Autodesk Fusion 360 part; units mm, degrees
(part 6 of 6)
sketch "Skizze11" plane through (0, 0, 0) normal (0, 1, 0) x (1, 0, 0)
  spline S0 degree 5 poles (100, -0.126) (99.9798, -0.1288) (99.9313, -0.1355) (99.8343, -0.1489) (99.6563, -0.1737) (99.3616, -0.2148) (99.015, -0.2631) (98.6371, -0.3154) (98.2386, -0.3703) (97.8209, -0.4275) (97.382, -0.4873) (96.9201, -0.55) (96.4368, -0.6152) (95.9348, -0.6827) (95.4173, -0.7517) (94.8865, -0.8221) (94.3434, -0.8935) (93.7883, -0.966) (93.2211, -1.0395) (92.6419, -1.1139) (92.0509, -1.1893) (91.4489, -1.2656) (90.8365, -1.3428) (90.2145, -1.4207) (89.5836, -1.4992) (88.9442, -1.5783) (88.2966, -1.6578) (87.6411, -1.7376) (86.9779, -1.8177) (86.3071, -1.898) (85.6291, -1.9785) (84.9441, -2.0592) (84.2524, -2.14) (83.5542, -2.2209) (82.8499, -2.302) (82.1396, -2.3832) (81.4237, -2.4644) (80.7023, -2.5455) (79.9756, -2.6264) (79.2439, -2.7072) (78.5072, -2.7876) (77.7658, -2.8678) (77.0199, -2.9476) (76.2696, -3.0272) (75.5151, -3.1065) (74.7565, -3.1855) (73.994, -3.2641) (73.2278, -3.3425) (72.458, -3.4204) (71.6848, -3.498) (70.9082, -3.5751) (70.1285, -3.6516) (69.3457, -3.7276) (68.5601, -3.8029) (67.7717, -3.8776) (66.9807, -3.9517) (66.1873, -4.025) (65.3915, -4.0976) (64.5935, -4.1695) (63.7933, -4.2406) (62.9912, -4.3109) (62.1872, -4.3803) (61.3815, -4.4489) (60.5741, -4.5165) (59.7651, -4.5832) (58.9548, -4.6489) (58.1431, -4.7135) (57.3303, -4.7772) (56.5164, -4.8397) (55.7016, -4.9011) (54.886, -4.9613) (54.0697, -5.0203) (53.2528, -5.078) (52.4355, -5.1344) (51.6179, -5.1895) (50.7999, -5.2432) (49.9819, -5.2955) (49.1638, -5.3463) (48.3457, -5.3956) (47.5278, -5.4433) (46.7102, -5.4895) (45.893, -5.5341) (45.0762, -5.577) (44.26, -5.6182) (43.4446, -5.6576) (42.63, -5.6953) (41.8164, -5.7311) (41.0039, -5.7649) (40.1926, -5.7967) (39.3826, -5.8264) (38.5742, -5.854) (37.7673, -5.8795) (36.9621, -5.9027) (36.1587, -5.9236) (35.3572, -5.9422) (34.5578, -5.9584) (33.7606, -5.9723) (32.9656, -5.9836) (32.1731, -5.9924) (31.3832, -5.9986) (30.596, -6.0021) (29.8117, -6.0029) (29.0304, -6.0008) (28.2522, -5.9958) (27.4773, -5.9879) (26.7059, -5.9771) (25.9381, -5.9631) (25.1741, -5.9461) (24.4139, -5.926) (23.6579, -5.9026) (22.9062, -5.876) (22.1589, -5.846) (21.4162, -5.8125) (20.6784, -5.7755) (19.9455, -5.7349) (19.218, -5.6907) (18.4958, -5.6427) (17.7792, -5.5908) (17.0686, -5.5351) (16.364, -5.4755) (15.6657, -5.4117) (14.974, -5.3438) (14.2893, -5.2716) (13.6117, -5.195) (12.9416, -5.1138) (12.2793, -5.028) (11.6251, -4.9374) (10.9794, -4.8419) (10.3425, -4.7414) (9.7148, -4.6358) (9.0967, -4.5249) (8.4888, -4.4086) (7.8916, -4.2868) (7.3058, -4.1591) (6.7319, -4.0253) (6.1705, -3.8852) (5.6223, -3.7383) (5.0877, -3.5844) (4.5676, -3.4228) (4.0631, -3.2534) (3.5755, -3.0757) (3.1066, -2.8893) (2.6585, -2.6938) (2.2329, -2.4884) (1.8313, -2.2718) (1.4554, -2.0423) (1.1078, -1.7986) (0.7933, -1.5393) (0.5196, -1.2639) (0.2958, -0.9725) (0.1296, -0.6653) (0.0462, -0.407) (0.012, -0.2062) (0.0019, -0.0693) (0, 0) knots 0 0 0 0 0 0 0.00666667 0.01333333 0.02 0.02666667 0.03333333 0.04 0.04666667 0.05333333 0.06 0.06666667 0.07333333 0.08 0.08666667 0.09333333 0.1 0.10666667 0.11333333 0.12 0.12666667 0.13333333 0.14 0.14666667 0.15333333 0.16 0.16666667 0.17333333 0.18 0.18666667 0.19333333 0.2 0.20666667 0.21333333 0.22 0.22666667 0.23333333 0.24 0.24666667 0.25333333 0.26 0.26666667 0.27333333 0.28 0.28666667 0.29333333 0.3 0.30666667 0.31333333 0.32 0.32666667 0.33333333 0.34 0.34666667 0.35333333 0.36 0.36666667 0.37333333 0.38 0.38666667 0.39333333 0.4 0.40666667 0.41333333 0.42 0.42666667 0.43333333 0.44 0.44666667 0.45333333 0.46 0.46666667 0.47333333 0.48 0.48666667 0.49333333 0.5 0.50666667 0.51333333 0.52 0.52666667 0.53333333 0.54 0.54666667 0.55333333 0.56 0.56666667 0.57333333 0.58 0.58666667 0.59333333 0.6 0.60666667 0.61333333 0.62 0.62666667 0.63333333 0.64 0.64666667 0.65333333 0.66 0.66666667 0.67333333 0.68 0.68666667 0.69333333 0.7 0.70666667 0.71333333 0.72 0.72666667 0.73333333 0.74 0.74666667 0.75333333 0.76 0.76666667 0.77333333 0.78 0.78666667 0.79333333 0.8 0.80666667 0.81333333 0.82 0.82666667 0.83333333 0.84 0.84666667 0.85333333 0.86 0.86666667 0.87333333 0.88 0.88666667 0.89333333 0.9 0.90666667 0.91333333 0.92 0.92666667 0.93333333 0.94 0.94666667 0.95333333 0.96 0.96666667 0.97333333 0.98 0.98666667 0.99333333 1 1 1 1 1 1
  spline S1 degree 5 poles (0, 0) (0.0019, 0.0693) (0.012, 0.2062) (0.0462, 0.407) (0.1296, 0.6653) (0.2958, 0.9725) (0.5196, 1.2639) (0.7933, 1.5393) (1.1078, 1.7986) (1.4554, 2.0423) (1.8313, 2.2718) (2.2329, 2.4884) (2.6585, 2.6938) (3.1066, 2.8893) (3.5755, 3.0757) (4.0631, 3.2534) (4.5676, 3.4228) (5.0877, 3.5844) (5.6223, 3.7383) (6.1705, 3.8852) (6.7319, 4.0253) (7.3058, 4.1591) (7.8916, 4.2868) (8.4888, 4.4086) (9.0967, 4.5249) (9.7148, 4.6358) (10.3425, 4.7414) (10.9794, 4.8419) (11.6251, 4.9374) (12.2793, 5.028) (12.9416, 5.1138) (13.6117, 5.195) (14.2893, 5.2716) (14.974, 5.3438) (15.6657, 5.4117) (16.364, 5.4755) (17.0686, 5.5351) (17.7792, 5.5908) (18.4958, 5.6427) (19.218, 5.6907) (19.9455, 5.7349) (20.6784, 5.7755) (21.4162, 5.8125) (22.1589, 5.846) (22.9062, 5.876) (23.6579, 5.9026) (24.4139, 5.926) (25.1741, 5.9461) (25.9381, 5.9631) (26.7059, 5.9771) (27.4773, 5.9879) (28.2522, 5.9958) (29.0304, 6.0008) (29.8117, 6.0029) (30.596, 6.0021) (31.3832, 5.9986) (32.1731, 5.9924) (32.9656, 5.9836) (33.7606, 5.9723) (34.5578, 5.9584) (35.3572, 5.9422) (36.1587, 5.9236) (36.9621, 5.9027) (37.7673, 5.8795) (38.5742, 5.854) (39.3826, 5.8264) (40.1926, 5.7967) (41.0039, 5.7649) (41.8164, 5.7311) (42.63, 5.6953) (43.4446, 5.6576) (44.26, 5.6182) (45.0762, 5.577) (45.893, 5.5341) (46.7102, 5.4895) (47.5278, 5.4433) (48.3457, 5.3956) (49.1638, 5.3463) (49.9819, 5.2955) (50.7999, 5.2432) (51.6179, 5.1895) (52.4355, 5.1344) (53.2528, 5.078) (54.0697, 5.0203) (54.886, 4.9613) (55.7016, 4.9011) (56.5164, 4.8397) (57.3303, 4.7772) (58.1431, 4.7135) (58.9548, 4.6489) (59.7651, 4.5832) (60.5741, 4.5165) (61.3815, 4.4489) (62.1872, 4.3803) (62.9912, 4.3109) (63.7933, 4.2406) (64.5935, 4.1695) (65.3915, 4.0976) (66.1873, 4.025) (66.9807, 3.9517) (67.7717, 3.8776) (68.5601, 3.8029) (69.3457, 3.7276) (70.1285, 3.6516) (70.9082, 3.5751) (71.6848, 3.498) (72.458, 3.4204) (73.2278, 3.3425) (73.994, 3.2641) (74.7565, 3.1855) (75.5151, 3.1065) (76.2696, 3.0272) (77.0199, 2.9476) (77.7658, 2.8678) (78.5072, 2.7876) (79.2439, 2.7072) (79.9756, 2.6264) (80.7023, 2.5455) (81.4237, 2.4644) (82.1396, 2.3832) (82.8499, 2.302) (83.5542, 2.2209) (84.2524, 2.14) (84.9441, 2.0592) (85.6291, 1.9785) (86.3071, 1.898) (86.9779, 1.8177) (87.6411, 1.7376) (88.2966, 1.6578) (88.9442, 1.5783) (89.5836, 1.4992) (90.2145, 1.4207) (90.8365, 1.3428) (91.4489, 1.2656) (92.0509, 1.1893) (92.6419, 1.1139) (93.2211, 1.0395) (93.7883, 0.966) (94.3434, 0.8935) (94.8865, 0.8221) (95.4173, 0.7517) (95.9348, 0.6827) (96.4368, 0.6152) (96.9201, 0.55) (97.382, 0.4873) (97.8209, 0.4275) (98.2386, 0.3703) (98.6371, 0.3154) (99.015, 0.2631) (99.3616, 0.2148) (99.6563, 0.1737) (99.8343, 0.1489) (99.9313, 0.1355) (99.9798, 0.1288) (100, 0.126) knots 0 0 0 0 0 0 0.00666667 0.01333333 0.02 0.02666667 0.03333333 0.04 0.04666667 0.05333333 0.06 0.06666667 0.07333333 0.08 0.08666667 0.09333333 0.1 0.10666667 0.11333333 0.12 0.12666667 0.13333333 0.14 0.14666667 0.15333333 0.16 0.16666667 0.17333333 0.18 0.18666667 0.19333333 0.2 0.20666667 0.21333333 0.22 0.22666667 0.23333333 0.24 0.24666667 0.25333333 0.26 0.26666667 0.27333333 0.28 0.28666667 0.29333333 0.3 0.30666667 0.31333333 0.32 0.32666667 0.33333333 0.34 0.34666667 0.35333333 0.36 0.36666667 0.37333333 0.38 0.38666667 0.39333333 0.4 0.40666667 0.41333333 0.42 0.42666667 0.43333333 0.44 0.44666667 0.45333333 0.46 0.46666667 0.47333333 0.48 0.48666667 0.49333333 0.5 0.50666667 0.51333333 0.52 0.52666667 0.53333333 0.54 0.54666667 0.55333333 0.56 0.56666667 0.57333333 0.58 0.58666667 0.59333333 0.6 0.60666667 0.61333333 0.62 0.62666667 0.63333333 0.64 0.64666667 0.65333333 0.66 0.66666667 0.67333333 0.68 0.68666667 0.69333333 0.7 0.70666667 0.71333333 0.72 0.72666667 0.73333333 0.74 0.74666667 0.75333333 0.76 0.76666667 0.77333333 0.78 0.78666667 0.79333333 0.8 0.80666667 0.81333333 0.82 0.82666667 0.83333333 0.84 0.84666667 0.85333333 0.86 0.86666667 0.87333333 0.88 0.88666667 0.89333333 0.9 0.90666667 0.91333333 0.92 0.92666667 0.93333333 0.94 0.94666667 0.95333333 0.96 0.96666667 0.97333333 0.98 0.98666667 0.99333333 1 1 1 1 1 1
  line L0 (100, 0.126) -> (100, -0.126)
  point P0 (99.726, -0.164)
  point P1 (98.907, -0.278)
  point P2 (97.553, -0.464)
  point P3 (95.677, -0.717)
  point P4 (93.301, -1.029)
  point P5 (90.451, -1.391)
  point P6 (87.157, -1.796)
  point P7 (83.457, -2.232)
  point P8 (79.389, -2.691)
  point P9 (75, -3.16)
  point P10 (70.337, -3.631)
  point P11 (65.451, -4.092)
  point P12 (60.396, -4.531)
  point P13 (55.226, -4.936)
  point P14 (50, -5.294)
  point P15 (44.774, -5.592)
  point P16 (39.604, -5.818)
  point P17 (34.549, -5.958)
  point P18 (29.663, -6.002)
  point P19 (25, -5.941)
  point P20 (20.611, -5.771)
  point P21 (16.544, -5.49)
  point P22 (12.843, -5.1)
  point P23 (9.549, -4.605)
  point P24 (6.699, -4.015)
  point P25 (4.323, -3.339)
  point P26 (2.447, -2.589)
  point P27 (1.093, -1.777)
  point P28 (0.274, -0.911)
  point P29 (0.274, 0.911)
  point P30 (1.093, 1.777)
  point P31 (2.447, 2.589)
  point P32 (4.323, 3.339)
  point P33 (6.699, 4.015)
  point P34 (9.549, 4.605)
  point P35 (12.843, 5.1)
  point P36 (16.544, 5.49)
  point P37 (20.611, 5.771)
  point P38 (25, 5.941)
  point P39 (29.663, 6.002)
  point P40 (34.549, 5.958)
  point P41 (39.604, 5.818)
  point P42 (44.774, 5.592)
  point P43 (50, 5.294)
  point P44 (55.226, 4.936)
  point P45 (60.396, 4.531)
  point P46 (65.451, 4.092)
  point P47 (70.337, 3.631)
  point P48 (75, 3.16)
  point P49 (79.389, 2.691)
  point P50 (83.457, 2.232)
  point P51 (87.157, 1.796)
  point P52 (90.451, 1.391)
  point P53 (93.301, 1.029)
  point P54 (95.677, 0.717)
  point P55 (97.553, 0.464)
  point P56 (98.907, 0.278)
  point P57 (99.726, 0.164)
surface "Schnitt_SLW_Wurzel" add patch profiles "Skizze11" section 1 separate body makes body 19
scale "Profiltiefe_SLW_Wurzel" factor 2.2 about (0, 0, 0) bodies 19
sketch "Skizze12" plane through (0, 0, 0) normal (0, 1, 0) x (1, 0, 0)
  spline S0 degree 5 poles (100, -0.126) (99.9798, -0.1288) (99.9313, -0.1355) (99.8343, -0.1489) (99.6563, -0.1737) (99.3616, -0.2148) (99.015, -0.2631) (98.6371, -0.3154) (98.2386, -0.3703) (97.8209, -0.4275) (97.382, -0.4873) (96.9201, -0.55) (96.4368, -0.6152) (95.9348, -0.6827) (95.4173, -0.7517) (94.8865, -0.8221) (94.3434, -0.8935) (93.7883, -0.966) (93.2211, -1.0395) (92.6419, -1.1139) (92.0509, -1.1893) (91.4489, -1.2656) (90.8365, -1.3428) (90.2145, -1.4207) (89.5836, -1.4992) (88.9442, -1.5783) (88.2966, -1.6578) (87.6411, -1.7376) (86.9779, -1.8177) (86.3071, -1.898) (85.6291, -1.9785) (84.9441, -2.0592) (84.2524, -2.14) (83.5542, -2.2209) (82.8499, -2.302) (82.1396, -2.3832) (81.4237, -2.4644) (80.7023, -2.5455) (79.9756, -2.6264) (79.2439, -2.7072) (78.5072, -2.7876) (77.7658, -2.8678) (77.0199, -2.9476) (76.2696, -3.0272) (75.5151, -3.1065) (74.7565, -3.1855) (73.994, -3.2641) (73.2278, -3.3425) (72.458, -3.4204) (71.6848, -3.498) (70.9082, -3.5751) (70.1285, -3.6516) (69.3457, -3.7276) (68.5601, -3.8029) (67.7717, -3.8776) (66.9807, -3.9517) (66.1873, -4.025) (65.3915, -4.0976) (64.5935, -4.1695) (63.7933, -4.2406) (62.9912, -4.3109) (62.1872, -4.3803) (61.3815, -4.4489) (60.5741, -4.5165) (59.7651, -4.5832) (58.9548, -4.6489) (58.1431, -4.7135) (57.3303, -4.7772) (56.5164, -4.8397) (55.7016, -4.9011) (54.886, -4.9613) (54.0697, -5.0203) (53.2528, -5.078) (52.4355, -5.1344) (51.6179, -5.1895) (50.7999, -5.2432) (49.9819, -5.2955) (49.1638, -5.3463) (48.3457, -5.3956) (47.5278, -5.4433) (46.7102, -5.4895) (45.893, -5.5341) (45.0762, -5.577) (44.26, -5.6182) (43.4446, -5.6576) (42.63, -5.6953) (41.8164, -5.7311) (41.0039, -5.7649) (40.1926, -5.7967) (39.3826, -5.8264) (38.5742, -5.854) (37.7673, -5.8795) (36.9621, -5.9027) (36.1587, -5.9236) (35.3572, -5.9422) (34.5578, -5.9584) (33.7606, -5.9723) (32.9656, -5.9836) (32.1731, -5.9924) (31.3832, -5.9986) (30.596, -6.0021) (29.8117, -6.0029) (29.0304, -6.0008) (28.2522, -5.9958) (27.4773, -5.9879) (26.7059, -5.9771) (25.9381, -5.9631) (25.1741, -5.9461) (24.4139, -5.926) (23.6579, -5.9026) (22.9062, -5.876) (22.1589, -5.846) (21.4162, -5.8125) (20.6784, -5.7755) (19.9455, -5.7349) (19.218, -5.6907) (18.4958, -5.6427) (17.7792, -5.5908) (17.0686, -5.5351) (16.364, -5.4755) (15.6657, -5.4117) (14.974, -5.3438) (14.2893, -5.2716) (13.6117, -5.195) (12.9416, -5.1138) (12.2793, -5.028) (11.6251, -4.9374) (10.9794, -4.8419) (10.3425, -4.7414) (9.7148, -4.6358) (9.0967, -4.5249) (8.4888, -4.4086) (7.8916, -4.2868) (7.3058, -4.1591) (6.7319, -4.0253) (6.1705, -3.8852) (5.6223, -3.7383) (5.0877, -3.5844) (4.5676, -3.4228) (4.0631, -3.2534) (3.5755, -3.0757) (3.1066, -2.8893) (2.6585, -2.6938) (2.2329, -2.4884) (1.8313, -2.2718) (1.4554, -2.0423) (1.1078, -1.7986) (0.7933, -1.5393) (0.5196, -1.2639) (0.2958, -0.9725) (0.1296, -0.6653) (0.0462, -0.407) (0.012, -0.2062) (0.0019, -0.0693) (0, 0) knots 0 0 0 0 0 0 0.00666667 0.01333333 0.02 0.02666667 0.03333333 0.04 0.04666667 0.05333333 0.06 0.06666667 0.07333333 0.08 0.08666667 0.09333333 0.1 0.10666667 0.11333333 0.12 0.12666667 0.13333333 0.14 0.14666667 0.15333333 0.16 0.16666667 0.17333333 0.18 0.18666667 0.19333333 0.2 0.20666667 0.21333333 0.22 0.22666667 0.23333333 0.24 0.24666667 0.25333333 0.26 0.26666667 0.27333333 0.28 0.28666667 0.29333333 0.3 0.30666667 0.31333333 0.32 0.32666667 0.33333333 0.34 0.34666667 0.35333333 0.36 0.36666667 0.37333333 0.38 0.38666667 0.39333333 0.4 0.40666667 0.41333333 0.42 0.42666667 0.43333333 0.44 0.44666667 0.45333333 0.46 0.46666667 0.47333333 0.48 0.48666667 0.49333333 0.5 0.50666667 0.51333333 0.52 0.52666667 0.53333333 0.54 0.54666667 0.55333333 0.56 0.56666667 0.57333333 0.58 0.58666667 0.59333333 0.6 0.60666667 0.61333333 0.62 0.62666667 0.63333333 0.64 0.64666667 0.65333333 0.66 0.66666667 0.67333333 0.68 0.68666667 0.69333333 0.7 0.70666667 0.71333333 0.72 0.72666667 0.73333333 0.74 0.74666667 0.75333333 0.76 0.76666667 0.77333333 0.78 0.78666667 0.79333333 0.8 0.80666667 0.81333333 0.82 0.82666667 0.83333333 0.84 0.84666667 0.85333333 0.86 0.86666667 0.87333333 0.88 0.88666667 0.89333333 0.9 0.90666667 0.91333333 0.92 0.92666667 0.93333333 0.94 0.94666667 0.95333333 0.96 0.96666667 0.97333333 0.98 0.98666667 0.99333333 1 1 1 1 1 1
  spline S1 degree 5 poles (0, 0) (0.0019, 0.0693) (0.012, 0.2062) (0.0462, 0.407) (0.1296, 0.6653) (0.2958, 0.9725) (0.5196, 1.2639) (0.7933, 1.5393) (1.1078, 1.7986) (1.4554, 2.0423) (1.8313, 2.2718) (2.2329, 2.4884) (2.6585, 2.6938) (3.1066, 2.8893) (3.5755, 3.0757) (4.0631, 3.2534) (4.5676, 3.4228) (5.0877, 3.5844) (5.6223, 3.7383) (6.1705, 3.8852) (6.7319, 4.0253) (7.3058, 4.1591) (7.8916, 4.2868) (8.4888, 4.4086) (9.0967, 4.5249) (9.7148, 4.6358) (10.3425, 4.7414) (10.9794, 4.8419) (11.6251, 4.9374) (12.2793, 5.028) (12.9416, 5.1138) (13.6117, 5.195) (14.2893, 5.2716) (14.974, 5.3438) (15.6657, 5.4117) (16.364, 5.4755) (17.0686, 5.5351) (17.7792, 5.5908) (18.4958, 5.6427) (19.218, 5.6907) (19.9455, 5.7349) (20.6784, 5.7755) (21.4162, 5.8125) (22.1589, 5.846) (22.9062, 5.876) (23.6579, 5.9026) (24.4139, 5.926) (25.1741, 5.9461) (25.9381, 5.9631) (26.7059, 5.9771) (27.4773, 5.9879) (28.2522, 5.9958) (29.0304, 6.0008) (29.8117, 6.0029) (30.596, 6.0021) (31.3832, 5.9986) (32.1731, 5.9924) (32.9656, 5.9836) (33.7606, 5.9723) (34.5578, 5.9584) (35.3572, 5.9422) (36.1587, 5.9236) (36.9621, 5.9027) (37.7673, 5.8795) (38.5742, 5.854) (39.3826, 5.8264) (40.1926, 5.7967) (41.0039, 5.7649) (41.8164, 5.7311) (42.63, 5.6953) (43.4446, 5.6576) (44.26, 5.6182) (45.0762, 5.577) (45.893, 5.5341) (46.7102, 5.4895) (47.5278, 5.4433) (48.3457, 5.3956) (49.1638, 5.3463) (49.9819, 5.2955) (50.7999, 5.2432) (51.6179, 5.1895) (52.4355, 5.1344) (53.2528, 5.078) (54.0697, 5.0203) (54.886, 4.9613) (55.7016, 4.9011) (56.5164, 4.8397) (57.3303, 4.7772) (58.1431, 4.7135) (58.9548, 4.6489) (59.7651, 4.5832) (60.5741, 4.5165) (61.3815, 4.4489) (62.1872, 4.3803) (62.9912, 4.3109) (63.7933, 4.2406) (64.5935, 4.1695) (65.3915, 4.0976) (66.1873, 4.025) (66.9807, 3.9517) (67.7717, 3.8776) (68.5601, 3.8029) (69.3457, 3.7276) (70.1285, 3.6516) (70.9082, 3.5751) (71.6848, 3.498) (72.458, 3.4204) (73.2278, 3.3425) (73.994, 3.2641) (74.7565, 3.1855) (75.5151, 3.1065) (76.2696, 3.0272) (77.0199, 2.9476) (77.7658, 2.8678) (78.5072, 2.7876) (79.2439, 2.7072) (79.9756, 2.6264) (80.7023, 2.5455) (81.4237, 2.4644) (82.1396, 2.3832) (82.8499, 2.302) (83.5542, 2.2209) (84.2524, 2.14) (84.9441, 2.0592) (85.6291, 1.9785) (86.3071, 1.898) (86.9779, 1.8177) (87.6411, 1.7376) (88.2966, 1.6578) (88.9442, 1.5783) (89.5836, 1.4992) (90.2145, 1.4207) (90.8365, 1.3428) (91.4489, 1.2656) (92.0509, 1.1893) (92.6419, 1.1139) (93.2211, 1.0395) (93.7883, 0.966) (94.3434, 0.8935) (94.8865, 0.8221) (95.4173, 0.7517) (95.9348, 0.6827) (96.4368, 0.6152) (96.9201, 0.55) (97.382, 0.4873) (97.8209, 0.4275) (98.2386, 0.3703) (98.6371, 0.3154) (99.015, 0.2631) (99.3616, 0.2148) (99.6563, 0.1737) (99.8343, 0.1489) (99.9313, 0.1355) (99.9798, 0.1288) (100, 0.126) knots 0 0 0 0 0 0 0.00666667 0.01333333 0.02 0.02666667 0.03333333 0.04 0.04666667 0.05333333 0.06 0.06666667 0.07333333 0.08 0.08666667 0.09333333 0.1 0.10666667 0.11333333 0.12 0.12666667 0.13333333 0.14 0.14666667 0.15333333 0.16 0.16666667 0.17333333 0.18 0.18666667 0.19333333 0.2 0.20666667 0.21333333 0.22 0.22666667 0.23333333 0.24 0.24666667 0.25333333 0.26 0.26666667 0.27333333 0.28 0.28666667 0.29333333 0.3 0.30666667 0.31333333 0.32 0.32666667 0.33333333 0.34 0.34666667 0.35333333 0.36 0.36666667 0.37333333 0.38 0.38666667 0.39333333 0.4 0.40666667 0.41333333 0.42 0.42666667 0.43333333 0.44 0.44666667 0.45333333 0.46 0.46666667 0.47333333 0.48 0.48666667 0.49333333 0.5 0.50666667 0.51333333 0.52 0.52666667 0.53333333 0.54 0.54666667 0.55333333 0.56 0.56666667 0.57333333 0.58 0.58666667 0.59333333 0.6 0.60666667 0.61333333 0.62 0.62666667 0.63333333 0.64 0.64666667 0.65333333 0.66 0.66666667 0.67333333 0.68 0.68666667 0.69333333 0.7 0.70666667 0.71333333 0.72 0.72666667 0.73333333 0.74 0.74666667 0.75333333 0.76 0.76666667 0.77333333 0.78 0.78666667 0.79333333 0.8 0.80666667 0.81333333 0.82 0.82666667 0.83333333 0.84 0.84666667 0.85333333 0.86 0.86666667 0.87333333 0.88 0.88666667 0.89333333 0.9 0.90666667 0.91333333 0.92 0.92666667 0.93333333 0.94 0.94666667 0.95333333 0.96 0.96666667 0.97333333 0.98 0.98666667 0.99333333 1 1 1 1 1 1
  line L0 (100, 0.126) -> (100, -0.126)
  point P0 (99.726, -0.164)
  point P1 (98.907, -0.278)
  point P2 (97.553, -0.464)
  point P3 (95.677, -0.717)
  point P4 (93.301, -1.029)
  point P5 (90.451, -1.391)
  point P6 (87.157, -1.796)
  point P7 (83.457, -2.232)
  point P8 (79.389, -2.691)
  point P9 (75, -3.16)
  point P10 (70.337, -3.631)
  point P11 (65.451, -4.092)
  point P12 (60.396, -4.531)
  point P13 (55.226, -4.936)
  point P14 (50, -5.294)
  point P15 (44.774, -5.592)
  point P16 (39.604, -5.818)
  point P17 (34.549, -5.958)
  point P18 (29.663, -6.002)
  point P19 (25, -5.941)
  point P20 (20.611, -5.771)
  point P21 (16.544, -5.49)
  point P22 (12.843, -5.1)
  point P23 (9.549, -4.605)
  point P24 (6.699, -4.015)
  point P25 (4.323, -3.339)
  point P26 (2.447, -2.589)
  point P27 (1.093, -1.777)
  point P28 (0.274, -0.911)
  point P29 (0.274, 0.911)
  point P30 (1.093, 1.777)
  point P31 (2.447, 2.589)
  point P32 (4.323, 3.339)
  point P33 (6.699, 4.015)
  point P34 (9.549, 4.605)
  point P35 (12.843, 5.1)
  point P36 (16.544, 5.49)
  point P37 (20.611, 5.771)
  point P38 (25, 5.941)
  point P39 (29.663, 6.002)
  point P40 (34.549, 5.958)
  point P41 (39.604, 5.818)
  point P42 (44.774, 5.592)
  point P43 (50, 5.294)
  point P44 (55.226, 4.936)
  point P45 (60.396, 4.531)
  point P46 (65.451, 4.092)
  point P47 (70.337, 3.631)
  point P48 (75, 3.16)
  point P49 (79.389, 2.691)
  point P50 (83.457, 2.232)
  point P51 (87.157, 1.796)
  point P52 (90.451, 1.391)
  point P53 (93.301, 1.029)
  point P54 (95.677, 0.717)
  point P55 (97.553, 0.464)
  point P56 (98.907, 0.278)
  point P57 (99.726, 0.164)
surface "Schnitt_SLW_1_Spitze" add patch profiles "Skizze12" section 1 separate body makes body 20
scale "Profiltiefe_SLW_1_Spitze" factor 1.4 about (0, 0, 0) bodies 20
move_body "Station_SLW_1" bodies 20 to x (1, 0, 0) y (0, 1, 0) z (0, 0, 1) at (35, 230, 0)
loft "Loft_SLW_1" add section 1 face at (75.9115, 0, 3.4252) section 2 face at (83.3073, 230, 2.1797) separate body on bodies 19 20 makes body 21
move_body "VForm_SLW" bodies 21 to x (1, 0, 0) y (0, 0, 1) z (0, -1, 0) at (0, 0, 0)
move_body "Position_SLW" bodies 21 to x (1, 0, 0) y (0, 1, 0) z (0, 0, 1) at (650, 0, 20)
delete_body "Körper entfernen11" bodies 19
delete_body "Körper entfernen12" bodies 20
equation "Tiefe_Wurzel = 255.0 mm" comment "Aus kobuz.flz"
equation "d2 = Tiefe_Wurzel / 100 mm"
equation "Breite_L1 = 60.0 mm" comment "Aus kobuz.flz"
equation "VForm_L1 = 0.0 deg" comment "Aus kobuz.flz"
equation "Tiefe_L1 = 255.0 mm" comment "Aus kobuz.flz"
equation "d6 = Tiefe_L1 / 100 mm"
equation "d8 = -( Breite_L1 * cos(VForm_L1) )"
equation "d9 = Breite_L1 * sin(VForm_L1)"
equation "Breite_L2 = 610.0 mm" comment "Aus kobuz.flz"
equation "VForm_L2 = 1.0 deg" comment "Aus kobuz.flz"
equation "Tiefe_L2 = 180.0 mm" comment "Aus kobuz.flz"
equation "d13 = Tiefe_L2 / 100 mm"
equation "d15 = -( Breite_L1 * cos(VForm_L1) + Breite_L2 * cos(VForm_L2) )"
equation "d16 = Breite_L1 * sin(VForm_L1) + Breite_L2 * sin(VForm_L2)"
equation "Breite_L3 = 610.0 mm" comment "Aus kobuz.flz"
equation "VForm_L3 = 1.0 deg" comment "Aus kobuz.flz"
equation "Tiefe_L3 = 105.0 mm" comment "Aus kobuz.flz"
equation "d20 = Tiefe_L3 / 100 mm"
equation "d22 = -( Breite_L1 * cos(VForm_L1) + Breite_L2 * cos(VForm_L2) + Breite_L3 * cos(VForm_L3) )"
equation "d23 = Breite_L1 * sin(VForm_L1) + Breite_L2 * sin(VForm_L2) + Breite_L3 * sin(VForm_L3)"
equation "Breite_R1 = 60.0 mm" comment "Aus kobuz.flz"
equation "VForm_R1 = 0.0 deg" comment "Aus kobuz.flz"
equation "Tiefe_R1 = 255.0 mm" comment "Aus kobuz.flz"
equation "d27 = Tiefe_R1 / 100 mm"
equation "d29 = ( Breite_R1 * cos(VForm_R1) )"
equation "d30 = Breite_R1 * sin(VForm_R1)"
equation "Breite_R2 = 610.0 mm" comment "Aus kobuz.flz"
equation "VForm_R2 = 1.0 deg" comment "Aus kobuz.flz"
equation "Tiefe_R2 = 180.0 mm" comment "Aus kobuz.flz"
equation "d34 = Tiefe_R2 / 100 mm"
equation "d36 = ( Breite_R1 * cos(VForm_R1) + Breite_R2 * cos(VForm_R2) )"
equation "d37 = Breite_R1 * sin(VForm_R1) + Breite_R2 * sin(VForm_R2)"
equation "Breite_R3 = 610 mm" comment "Aus kobuz.flz"
equation "VForm_R3 = 1 deg" comment "Aus kobuz.flz"
equation "Tiefe_R3 = 105 mm" comment "Aus kobuz.flz"
equation "d41 = Tiefe_R3 / 100 mm"
equation "d43 = ( Breite_R1 * cos(VForm_R1) + Breite_R2 * cos(VForm_R2) + Breite_R3 * cos(VForm_R3) )"
equation "d44 = Breite_R1 * sin(VForm_R1) + Breite_R2 * sin(VForm_R2) + Breite_R3 * sin(VForm_R3)"
equation "HLW_X = 720.0 mm" comment "Aus kobuz.flz"
equation "HLW_Y = 0.0 mm" comment "Aus kobuz.flz"
equation "HLW_Z = 0.0 mm" comment "Aus kobuz.flz"
equation "HLW_Einstellwinkel = -1 deg" comment "Aus kobuz.flz"
equation "HLW_Tiefe_Wurzel = 140.0 mm" comment "Aus kobuz.flz"
equation "d50 = HLW_Tiefe_Wurzel / 100 mm"
equation "HLW_1_Breite = 285.0 mm" comment "Aus kobuz.flz"
equation "HLW_1_Tiefe = 100.0 mm" comment "Aus kobuz.flz"
equation "HLW_1_Pfeilung = 3.61388 deg" comment "Aus kobuz.flz"
equation "HLW_1_VForm = 0.00000 deg" comment "Aus kobuz.flz"
equation "d55 = HLW_1_Tiefe / 100 mm"
equation "d56 = HLW_1_Breite * tan(HLW_1_Pfeilung)"
equation "d57 = -HLW_1_Breite"
equation "HLW_2_Breite = 285.0 mm" comment "Aus kobuz.flz"
equation "HLW_2_Tiefe = 100 mm" comment "Aus kobuz.flz"
equation "HLW_2_Pfeilung = 3.61388 deg" comment "Aus kobuz.flz"
equation "HLW_2_VForm = 0.00000 deg" comment "Aus kobuz.flz"
equation "d63 = HLW_2_Tiefe / 100 mm"
equation "d64 = HLW_2_Breite * tan(HLW_2_Pfeilung)"
equation "d65 = HLW_2_Breite"
equation "d67 = HLW_Einstellwinkel"
equation "d68 = HLW_X"
equation "d69 = HLW_Y"
equation "d70 = HLW_Z"
equation "SLW_X = 650.0 mm" comment "Aus kobuz.flz"
equation "SLW_Y = 0.0 mm" comment "Aus kobuz.flz"
equation "SLW_Z = 20.0 mm" comment "Aus kobuz.flz"
equation "SLW_Einstellwinkel = 0.00000 deg" comment "Aus kobuz.flz"
equation "SLW_Tiefe_Wurzel = 220.0 mm" comment "Aus kobuz.flz"
equation "d76 = SLW_Tiefe_Wurzel / 100 mm"
equation "SLW_1_Breite = 230 mm" comment "Aus kobuz.flz"
equation "SLW_1_Tiefe = 140.0 mm" comment "Aus kobuz.flz"
equation "SLW_1_Pfeilung = 8.65254 deg" comment "Aus kobuz.flz"
equation "SLW_1_VForm = 90.00000 deg" comment "Aus kobuz.flz"
equation "d81 = SLW_1_Tiefe / 100 mm"
equation "d82 = SLW_1_Breite * tan(SLW_1_Pfeilung)"
equation "d83 = SLW_1_Breite"
equation "d85 = SLW_1_VForm"
equation "d86 = SLW_X"
equation "d87 = SLW_Y"
equation "d88 = SLW_Z"
named bodies: "Hilfsprofil_Mitte", "Hilfsprofil_L1", "Hilfsprofil_L2", "Hilfsprofil_L3", "Hilfsprofil_R1", "Hilfsprofil_R2", "Hilfsprofil_R3", "Kobuz_Tragfluegel_Gesamt", "Fluegelsegment_L2", "Fluegelsegment_L3", "Fluegelsegment_R1", "Fluegelsegment_R2", "Fluegelsegment_R3", "Hilfsprofil_HLW_Wurzel", "Hilfsprofil_HLW_1_Spitze", "Horizontal_Stabilizer", "Hilfsprofil_HLW_2_Spitze", "Hilfsprofil_SLW_Wurzel", "Hilfsprofil_SLW_1_Spitze", "Vertical_Fin"
